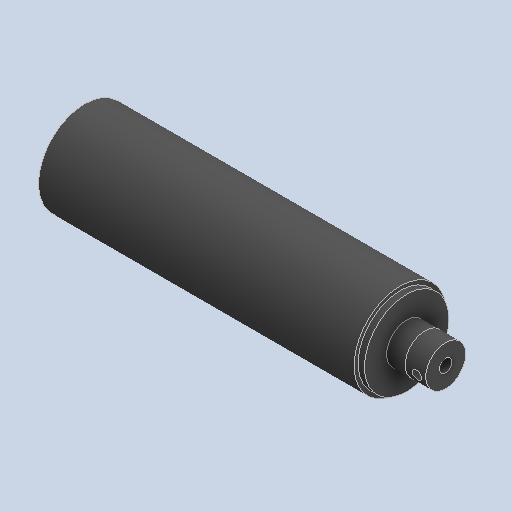
# Autodesk Inventor part: rodillo con rodamiento
Saved by Autodesk Inventor 2025.3 (Build 293356000, 356)
## iProperties
Created: 2026-09-21
Part Number: rodillo con rodamiento
Material: Acetal POM-C (referencia nominal)
Document SubType Name: Modeling
Designer: ASUS
Density: 1.41 g/cm^3
Appearance: Genérico
Mass: 106.452 g
Surface Area: 117.578 cm^2
Volume: 75.4977 cm^3
Author: ASUS
Autodesk Inventor part; units mm, degrees
sketch "Boceto1" plane through (0, 0, 0) normal (1, 0, 0) x (0, 1, 0)
  circle A0 centre (0, 0) radius 15
  dimension "d0" = 30
  constraints: 1 centre point, 1 coincident
  measures "d0" diameter of A0
extrude "Extrusión1" add sketch "Boceto1" along normal blind 104.554
sketch "Boceto2" plane through (104.554, 0, 0) normal (1, 0, 0) x (0, 0, -1)
  circle A0 centre (0, 0) radius 6.5
  dimension "d3" = 13
  constraints: 1 centre point, 1 coincident
  measures "d3" diameter of A0
extrude "Extrusión2" add sketch "Boceto2" along normal blind 6
sketch "Boceto3" plane through (0, 0, 0) normal (-1, 0, 0) x (0, 0, 1)
  circle A0 centre (0, 0) radius 6.5
  dimension "d6" = 13
  constraints: 1 centre point, 1 coincident
  measures "d6" diameter of A0
extrude "Extrusión3" add sketch "Boceto3" along normal blind 6
ref_plane "Cota original del extremo motriz" through (110.554, 0, 0) normal (1, 0, 0) x (0, 0, -1)
sketch "Boceto4" plane through (110.554, 0, 0) normal (1, 0, 0) x (0, 0, -1)
  circle A0 centre (0, 0) radius 6.5
  dimension "d9" = 6.5
  constraints: 1 centre point
  measures "d9" radius of A0
extrude "Extensión coaxial D4" add sketch "Boceto4" along normal blind 6.7
ref_plane "Frente paramétrico del alojamiento D4" through (117.254, 0, 0) normal (1, 0, 0) x (0, 0, -1)
sketch "Boceto5" plane through (117.254, 0, 0) normal (1, 0, 0) x (0, 0, -1)
  circle A0 centre (0, 0) radius 2.05
  dimension "d13" = 2.05
  constraints: 1 centre point
  measures "d13" radius of A0
extrude "Alojamiento axial para el D4" cut sketch "Boceto5" against normal blind 6.25
ref_plane "Inicio de alivio exterior a la huella de banda" through (102.484, 0, 0) normal (1, 0, 0) x (0, 0, -1)
sketch "Boceto6" plane through (102.484, 0, 0) normal (1, 0, 0) x (0, 0, -1)
  circle A0 centre (0, 0) radius 15.2
  circle A1 centre (0, 0) radius 13.7
  dimension "d16" = 13.7
  constraints: 2 centre point
  measures "d16" radius of A1
extrude "Alivio del hombro contra el alojamiento grande" cut sketch "Boceto6" along normal blind 2.09
ref_plane "Datum radial en el plano D" through (114.254, -1.084, 6.6117) normal (0, -0.1618, 0.9868) x (0, -0.9868, -0.1618)
sketch "Boceto7" plane through (114.254, -1.084, 6.6117) normal (0, -0.1618, 0.9868) x (0, -0.9868, -0.1618)
  circle A0 centre (0, 0) radius 1.525
  dimension "d19" = 1.525
  constraints: 1 centre point
  measures "d19" radius of A0
extrude "Alojamiento radial del prisionero M3" cut sketch "Boceto7" against normal blind 5.6
ref_plane "Referencia angular de arrastre D4" through (0, 0, 0) normal (0, -0.9868, -0.1618) x (0, 0.1618, -0.9868)
equation "\"d9\" = 0.5 * Diametro_extremo"
equation "\"d10\" = Extension_acople"
equation "\"d13\" = 0.5 * Diametro_alojamiento_D4"
equation "\"d14\" = Profundidad_taladro"
equation "\"d16\" = 0.5 * Diametro_alivio"
equation "\"d17\" = Longitud_alivio"
equation "\"d19\" = 0.5 * Diametro_envolvente_M3"
equation "\"Brecha_V21\" = 0.7"
equation "\"Insercion_D4\" = 6"
equation "\"Extension_acople\" = Insercion_D4 + Brecha_V21"
equation "\"Fondo_seguridad\" = 0.25"
equation "\"Profundidad_taladro\" = Insercion_D4 + Fondo_seguridad"
equation "\"Diametro_alojamiento_D4\" = 4.1"
equation "\"Diametro_extremo\" = 13"
equation "\"Diametro_envolvente_M3\" = 3.05"
equation "\"Longitud_alivio\" = 2.09"
equation "\"Diametro_alivio\" = 27.4"
equation "\"d12\" = Extension_acople"
